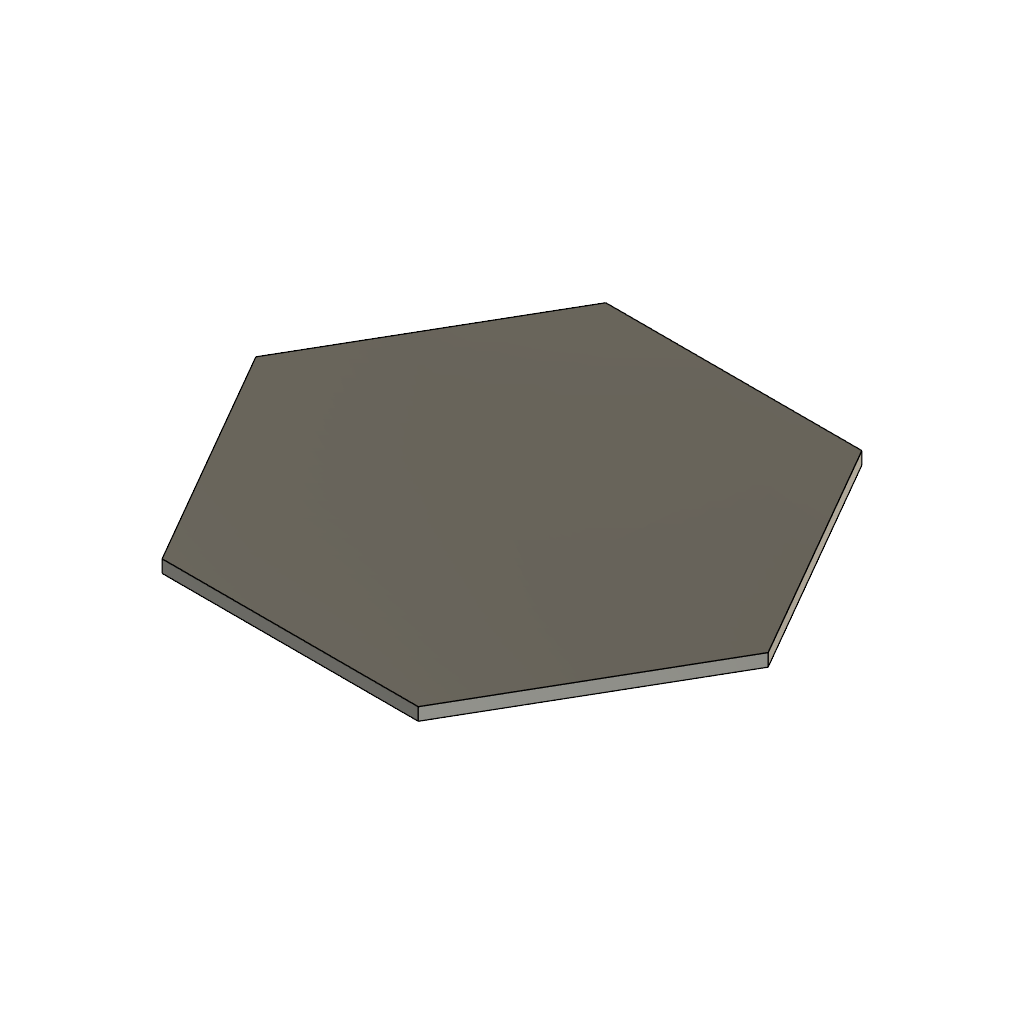
DicePopperPlate (Autodesk Fusion 360 design; units mm, degrees)
Autodesk Fusion 360 part; units mm, degrees
sketch "Sketch1" plane through (0, 0, 0) normal (0, 0, 1) x (1, 0, 0)
  line L0 (-30.3109, 52.5) -> (-60.6218, 0)
  line L1 (-60.6218, 0) -> (-30.3109, -52.5)
  line L2 (-30.3109, -52.5) -> (30.3109, -52.5)
  line L3 (30.3109, -52.5) -> (60.6218, 0)
  line L4 (60.6218, 0) -> (30.3109, 52.5)
  line L5 (30.3109, 52.5) -> (-30.3109, 52.5)
  dimension "d1" = 52.5
  measures "d1" distance of origin L5
extrude "Extrude1" add sketch "Sketch1" along normal blind 3
